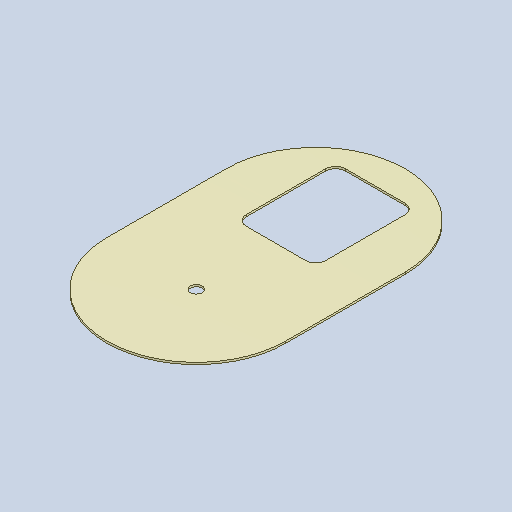
# Autodesk Inventor part: RDS-1103 Tank Top Cover PP
Saved by Autodesk Inventor 2026.2 (Build 302298000, 298)
## iProperties
Created: 2026-10-18
Part Number: RDS-1103 Tank Top Cover PP
Material: Polypropylene
Description: Tank top cover, polypropylene: access hatch 500x400 R50, mixer hole near end
Document SubType Name: Modeling
Designer: admin
Stock Number: Верхняя крышка ёмкости ПП
Density: 0.899 g/cm^3
Appearance: Smooth - Ash
Author: admin
Autodesk Inventor part; units mm, degrees
ref_plane "YZ Plane" through (0, 0, 0) normal (1, 0, 0) x (0, 1, 0)
ref_plane "XZ Plane" through (0, 0, 0) normal (0, 1, 0) x (-1, 0, 0)
ref_plane "XY Plane" through (0, 0, 0) normal (0, 0, 1) x (1, 0, 0)
sketch "Sketch1" plane through (0, 0, 0) normal (0, 1, 0) x (-1, 0, 0)
  line L0 (-450, -300) -> (-450, 300)
  line L1 (450, 300) -> (450, -300)
  arc A0 (450, 300) -> (-450, 300) centre (0, 300) ccw
  arc A1 (-450, -300) -> (450, -300) centre (0, -300) ccw
  dimension "d0" = 450
  dimension "d1" = 600
  constraints: 4 end point, 4 point on circle, 4 tangent, 2 centre point, 1 equal radius
  measures "d0" radius of A0
  measures "d1" distance of L0.start L0.end
extrude "Plate" add sketch "Sketch1" along normal blind 10
sketch "Sketch2" plane through (0, 10, 0) normal (0, 1, 0) x (1, 0, 0)
  circle A0 centre (0, -300) radius 30
  line L0 (-200, 600) -> (200, 600)
  line L1 (200, 600) -> (200, 100)
  line L2 (200, 100) -> (-200, 100)
  line L3 (-200, 100) -> (-200, 600)
  dimension "d5" = 60
  constraints: 8 end point, 2 parallel, 1 centre point, 1 horizontal, 1 perpendicular
  measures "d5" diameter of A0
extrude "Access Hatch and Mixer Hole" cut sketch "Sketch2" along normal through all both and the other way through all
fillet "Access Hatch Fillet" radius 50 4 edges at (-200, 5, -600) (-200, 5, -100) (200, 5, -100) (200, 5, -600)
equation "\"d0\" = 0.5 * Top1103_Width"
equation "\"d1\" = Top1103_Length - Top1103_Width"
equation "\"d2\" = Top1103_Thickness"
equation "\"d5\" = Top1103_Mixer_Hole_Diam"
equation "\"d8\" = Top1103_Access_Hatch_Fillet_Radius"
equation "\"Top1103_Length\" = 1500"
equation "\"Top1103_Width\" = 900"
equation "\"Top1103_Thickness\" = 10"
equation "\"Top1103_Mixer_Hole_Diam\" = 60"
equation "\"Top1103_Access_Hatch_Fillet_Radius\" = 50"
body "Solid1"
